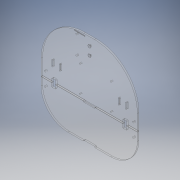
# Autodesk Inventor part: Chassis
Saved by Autodesk Inventor 2019.4 (Build 234330000, 330)
## iProperties
Created: 2020-09-02
Part Number: Chassis
Material: PMMA Plastic
Document SubType Name: Modeling
Designer: Mike Angus
Density: 1.188 g/cm^3
Appearance: Polycarbonate - Clear
ch_motorHoleSpacing: 25,200 mm
ch_motorHoleOffset: 7,500 mm
ch_motorHoleDiam: 3,000 mm
Author: Mike Angus
Autodesk Inventor part; units mm, degrees
ref_plane "YZ Plane" through (0, 0, 0) normal (1, 0, 0) x (0, 1, 0)
ref_plane "XZ Plane" through (0, 0, 0) normal (0, 1, 0) x (-1, 0, 0)
ref_plane "XY Plane" through (0, 0, 0) normal (0, 0, 1) x (1, 0, 0)
sketch "Profielt" plane through (0, 0, 0) normal (0, 0, 1) x (1, 0, 0)
  line L0 (90, 0) -> (-90, 0)
  line L1 (-90, 0) -> (-90, -65)
  line L2 (-90, -65) -> (90, -65)
  line L3 (90, -65) -> (90, 0)
  line L4 (90, 0) -> (90, 110)
  line L5 (90, 110) -> (-90, 110)
  line L6 (-90, 110) -> (-90, 0)
  point P0 (0, 0)
  point P1 (0, 0)
  point P2 (0, 0)
  dimension "d9" = 65
  dimension "d10" = 180
  dimension "d11" = 110
  constraints: 14 end point, 3 perpendicular, 2 parallel, 1 coincident, 1 horizontal, 1 midpoint, 1 vertical
  measures "d9" distance of L2.end L0.start
  measures "d10" distance of L1.end L2.end
  measures "d11" distance of L0.start L4.end
extrude "Front" add sketch "Profielt" along normal blind 3 contours L0 L6 L5 L4
extrude "Rear" add sketch "Profielt" along normal blind 3 separate body contours L3 L2 L1 L0
sketch "Sketch8" plane through (-90, 0, 0) normal (0, 1, 0) x (1, 0, 0)
  line L0 (180, 0) -> (0, 0) projected
  line L1 (0, 0) -> (0, -3) projected
  line L2 (180, -3) -> (0, -3) projected
  line L3 (180, 0) -> (180, -3) projected
  point P0 (90, 0)
extrude "Extrusion10" add sketch "Sketch8" along normal blind 0.4 bodies 2
fillet "Outer Fillets" radius 80 2 edges at (-90, 110, 1.5) (90, 110, 1.5)
fillet "Outer Fillets" radius 50 2 edges at (90, -65, 1.5) (-90, -65, 1.5)
sketch "Sketch2" plane through (0, 0, 3) normal (0, 0, 1) x (1, 0, 0)
  line L0 (0, 0) -> (-82.5, 0) construction
  line L1 (-82.5, -12.6) -> (-82.5, 12.6) construction
  circle A0 centre (-82.5, 12.6) radius 1.5
  circle A1 centre (-82.5, -12.6) radius 1.5
  line L2 (0, 0) -> (0, -16.3555) construction
  circle A2 centre (82.5, 12.6) radius 1.5
  circle A3 centre (82.5, -12.6) radius 1.5
  dimension "d12" = 82.5
  dimension "d13" = 25.2
  dimension "d14" = 3
  constraints: 6 end point, 4 centre point, 2 coincident, 2 symmetric about line, 2 vertical, 1 equal radius, 1 horizontal, 1 midpoint, 2 other
  measures "d12" distance of L0.end L0.start
  measures "d13" distance of L1.start L1.end
  measures "d14" diameter of A0
extrude "Motor Holes" cut sketch "Sketch2" against normal through all bodies 2 1
sketch "Sketch3" plane through (0, 0, 3) normal (0, 0, 1) x (1, 0, 0)
  line L0 (40.5, 57) -> (-17.5, 57) construction
  line L1 (-17.5, 57) -> (-17.5, 8) construction
  line L2 (-17.5, 8) -> (40.5, 8) construction
  line L3 (40.5, 8) -> (40.5, 57) construction
  circle A0 centre (40.5, 8) radius 1.25
  circle A1 centre (-17.5, 8) radius 1.25
  circle A2 centre (-17.5, 57) radius 1.25
  circle A3 centre (40.5, 57) radius 1.25
  line L4 (0, 8) -> (0, 0) construction
  point P0 (11.5, 8)
  dimension "d18" = 49
  dimension "d19" = 58
  dimension "d20" = 2.5
  dimension "d21" = 2.5
  dimension "d22" = 2.5
  dimension "d23" = 2.5
  dimension "d26" = 8
  dimension "d27" = 11.5
  constraints: 10 end point, 5 coincident, 4 centre point, 2 parallel, 1 horizontal, 1 midpoint, 1 perpendicular, 1 point on line, 1 vertical
  measures "d18" distance of L0.end L1.end
  measures "d19" distance of L0.start L0.end
  measures "d20" diameter of A0
  measures "d21" diameter of A1
  measures "d22" diameter of A2
  measures "d23" diameter of A3
  measures "d26" distance of L4.start L4.end
  measures "d27" distance from line of L4 point (11.5, 8)
extrude "Pi holes" cut sketch "Sketch3" against normal through all bodies 1
sketch "Castor holes/nuts" plane through (0, 0, 3) normal (0, 0, 1) x (1, 0, 0)
  line L0 (0, 0) -> (0, 94) construction
  line L1 (0, 78.6) -> (0, 94) construction
  circle A0 centre (0, 78.6) radius 1.25
  circle A1 centre (0, 94) radius 1.25
  line L2 (-2.829, 94) -> (-1.4145, 96.45)
  line L3 (-1.4145, 96.45) -> (1.4145, 96.45)
  line L4 (1.4145, 96.45) -> (2.829, 94)
  line L5 (2.829, 94) -> (1.4145, 91.55)
  line L6 (1.4145, 91.55) -> (-1.4145, 91.55)
  line L7 (-1.4145, 91.55) -> (-2.829, 94)
  line L8 (1.4145, 76.15) -> (-1.4145, 76.15)
  line L9 (-1.4145, 76.15) -> (-2.829, 78.6)
  line L10 (-2.829, 78.6) -> (-1.4145, 81.05)
  line L11 (-1.4145, 81.05) -> (1.4145, 81.05)
  line L12 (1.4145, 81.05) -> (2.829, 78.6)
  line L13 (2.829, 78.6) -> (1.4145, 76.15)
  dimension "d28" = 94
  dimension "d29" = 15.4
  dimension "d30" = 2.5
  dimension "d31" = 2.5
  dimension "d34" = 4.9
  dimension "d35" = 4.9
  constraints: 28 end point, 4 coincident, 2 centre point, 2 horizontal, 2 vertical, 26 other
  measures "d28" distance of L0.end L0.start
  measures "d29" distance of L0.end L1.start
  measures "d30" diameter of A0
  measures "d31" diameter of A1
  measures "d34" distance between parallel lines of L3 L6
  measures "d35" distance between parallel lines of L8 L11
extrude "Castor holes" cut sketch "Castor holes/nuts" against normal through all contours A0 | A1 bodies 1
extrude "Castor nut cuts" cut sketch "Castor holes/nuts" against normal blind 1 bodies 1
sketch "Camera holes and slot" plane through (0, 0, 0) normal (0, 0, -1) x (-1, 0, 0)
  line L0 (0, 0) -> (0, 102) construction
  line L1 (0, 102) -> (23.73, 102) construction
  line L2 (23.73, 102) -> (23.73, 67) construction
  circle A0 centre (23.73, 67) radius 1.5
  circle A1 centre (23.73, 102) radius 1.5
  line L3 (8.23, 105.8) -> (27.73, 105.8)
  line L4 (27.73, 105.8) -> (27.73, 107.05)
  line L5 (27.73, 107.05) -> (8.23, 107.05)
  line L6 (8.23, 107.05) -> (8.23, 105.8)
  line L7 (8.23, 105.8) -> (27.73, 107.05) construction
  line L8 (27.73, 105.8) -> (8.23, 107.05) construction
  line L9 (23.73, 102) -> (27.73, 102) construction
  line L10 (27.73, 102) -> (27.73, 105.8) construction
  point P0 (17.98, 106.425)
  dimension "d38" = 102
  dimension "d39" = 23.73
  dimension "d40" = 35
  dimension "d41" = 3
  dimension "d42" = 3
  dimension "d45" = 19.5
  dimension "d46" = 1.25
  dimension "d47" = 4
  dimension "d48" = 3.8
  constraints: 22 end point, 3 perpendicular, 2 centre point, 2 coincident, 2 horizontal, 2 midpoint, 2 parallel, 2 vertical
  measures "d38" distance of L0.start L0.end
  measures "d39" distance of L0.end L1.end
  measures "d40" distance of L1.end L2.end
  measures "d41" diameter of A0
  measures "d42" diameter of A1
  measures "d45" distance of L5.end L4.end
  measures "d46" distance of L3.end L4.end
  measures "d47" distance of L9.start L9.end
  measures "d48" distance of L9.end L3.end
extrude "Extrusion7" cut sketch "Camera holes and slot" against normal through all contours A0 | A1 bodies 1
sketch "Sketch6" plane through (0, 0, 3) normal (0, 0, 1) x (1, 0, 0)
  line L0 (-8.23, 105.8) -> (-27.73, 105.8) projected
  line L1 (-8.23, 107.05) -> (-8.23, 105.8) projected
  line L2 (-27.73, 107.05) -> (-8.23, 107.05) projected
  line L3 (-27.73, 105.8) -> (-27.73, 107.05) projected
  point P0 (0, 0)
extrude "Extrusion8" cut sketch "Sketch6" against normal blind 0.5 bodies 1
sketch "Slots" plane through (0, 0, 3) normal (0, 0, 1) x (1, 0, 0)
  line L0 (-64, -7.1) -> (-69, -7.1)
  line L1 (-70, -6.1) -> (-70, 6.9)
  line L2 (-69, 7.9) -> (-64, 7.9)
  line L3 (-63, 6.9) -> (-63, -6.1)
  line L4 (-63, -7.1) -> (-70, 7.9) construction
  line L5 (-70, -7.1) -> (-63, 7.9) construction
  line L6 (-70, 0.4) -> (0, 0.4) construction
  arc A0 (-64, -7.1) -> (-63, -6.1) centre (-64, -6.1) ccw
  arc A1 (-70, -6.1) -> (-69, -7.1) centre (-69, -6.1) ccw
  arc A2 (-69, 7.9) -> (-70, 6.9) centre (-69, 6.9) ccw
  arc A3 (-63, 6.9) -> (-64, 7.9) centre (-64, 6.9) ccw
  line L7 (0, 0.4) -> (0, -65) construction
  line L8 (64, -7.1) -> (69, -7.1)
  line L9 (70, -6.1) -> (70, 6.9)
  line L10 (69, 7.9) -> (64, 7.9)
  line L11 (63, 6.9) -> (63, -6.1)
  line L12 (63, -7.1) -> (70, 7.9) construction
  line L13 (70, -7.1) -> (63, 7.9) construction
  arc A4 (63, -6.1) -> (64, -7.1) centre (64, -6.1) ccw
  arc A5 (69, -7.1) -> (70, -6.1) centre (69, -6.1) ccw
  arc A6 (70, 6.9) -> (69, 7.9) centre (69, 6.9) ccw
  arc A7 (64, 7.9) -> (63, 6.9) centre (64, 6.9) ccw
  line L14 (10.5, -1.6) -> (-10.5, -1.6)
  line L15 (-10.5, -1.6) -> (-10.5, 0.4)
  line L16 (-10.5, 0.4) -> (10.5, 0.4)
  line L17 (10.5, 0.4) -> (10.5, -1.6)
  line L18 (10.5, -1.6) -> (-10.5, 0.4) construction
  line L19 (-10.5, -1.6) -> (10.5, 0.4) construction
  line L20 (10.5, -65) -> (-10.5, -65)
  line L21 (-10.5, -65) -> (-10.5, -63)
  line L22 (-10.5, -63) -> (10.5, -63)
  line L23 (10.5, -63) -> (10.5, -65)
  line L24 (10.5, -65) -> (-10.5, -63) construction
  line L25 (-10.5, -65) -> (10.5, -63) construction
  point P0 (70, 0.4)
  point P1 (0, -0.6)
  point P2 (0, -0.6)
  point P3 (0, -64)
  point P4 (0, -64)
  point P5 (0, 0)
  dimension "d51" = 7
  dimension "d52" = 15
  dimension "d53" = 70
  dimension "d54" = 1
  dimension "d55" = 1
  dimension "d56" = 21
  dimension "d57" = 2
  dimension "d58" = 65.4
  dimension "d59" = 21
  dimension "d60" = 2
  dimension "d66" = 0.4
  constraints: 52 end point, 19 point on line, 17 symmetric about line, 16 point on circle, 9 midpoint, 8 centre point, 8 tangent, 6 parallel, 4 horizontal, 3 perpendicular, 2 equal radius, 1 coincident, 1 vertical, 4 other
  measures "d51" distance of L4.end L5.end
  measures "d52" distance of L5.start L4.end
  measures "d53" distance of L6.start L6.end
  measures "d54" radius of A0
  measures "d55" radius of A3
  measures "d56" distance of L14.start L14.end
  measures "d57" distance of L14.end L15.end
  measures "d58" distance of L7.end L6.end
  measures "d59" distance of L21.end L22.end
  measures "d60" distance of L20.end L21.end
  measures "d66" distance from line of point (0, 0) L16
extrude "Velcro batt slot" cut sketch "Slots" against normal through all contours L14 L15 L16 L17 | L20 L21 L22 L23 bodies 2
extrude "Motor slots" cut sketch "Slots" against normal through all contours L0 A1 L1 A2 L2 A3 L3 A0 | A4 L11 A7 L10 A6 L9 A5 L8 bodies 2 1
fillet "Fillet2" radius 1 8 edges at (10.5, -1.6, 1.5) (-10.5, -1.6, 1.5) (-10.5, -65, 1.5) (-10.5, -63, 1.5) (10.5, -63, 1.5) (10.5, -65, 1.5) (10.5, 0.4, 1.5) (-10.5, 0.4, 1.5)
sketch "Sketch9" plane through (0, 0, 3) normal (0, 0, 1) x (1, 0, 0)
  line L0 (0, 0) -> (0, 32) construction
  line L1 (0, 32) -> (-55, 32) construction
  line L2 (-55, 27) -> (-55, 37) construction
  line L3 (-54, 27) -> (-54, 37)
  line L4 (-56, 37) -> (-56, 27)
  arc A0 (-56, 27) -> (-54, 27) centre (-55, 27) ccw
  arc A1 (-54, 37) -> (-56, 37) centre (-55, 37) ccw
  line L5 (-55, 32) -> (-69, 32) construction
  line L6 (-69, 27) -> (-69, 37) construction
  line L7 (-68, 27) -> (-68, 37)
  line L8 (-70, 37) -> (-70, 27)
  arc A2 (-70, 27) -> (-68, 27) centre (-69, 27) ccw
  arc A3 (-68, 37) -> (-70, 37) centre (-69, 37) ccw
  line L9 (55, 27) -> (55, 37) construction
  line L10 (54, 27) -> (54, 37)
  line L11 (56, 37) -> (56, 27)
  arc A4 (54, 27) -> (56, 27) centre (55, 27) ccw
  arc A5 (56, 37) -> (54, 37) centre (55, 37) ccw
  line L12 (55, 32) -> (69, 32) construction
  line L13 (69, 27) -> (69, 37) construction
  line L14 (68, 27) -> (68, 37)
  line L15 (70, 37) -> (70, 27)
  arc A6 (68, 27) -> (70, 27) centre (69, 27) ccw
  arc A7 (70, 37) -> (68, 37) centre (69, 37) ccw
  dimension "d67" = 32
  dimension "d68" = 55
  dimension "d70" = 2
  dimension "d71" = 14
  dimension "d73" = 10
  dimension "d74" = 10
  dimension "d75" = 2
  constraints: 40 end point, 16 point on circle, 14 symmetric about line, 8 centre point, 8 tangent, 3 vertical, 2 midpoint, 2 parallel, 1 horizontal, 1 perpendicular, 4 other
  measures "d67" distance of L0.start L0.end
  measures "d68" distance of L0.end L1.end
  measures "d70" diameter of A1
  measures "d71" distance of L1.end L5.end
  measures "d73" distance of L2.start L2.end
  measures "d74" distance of L6.start L6.end
  measures "d75" distance between parallel lines of L8 L7
extrude "Extrusion11" cut sketch "Sketch9" against normal through all bodies 1
equation "\"d9\" = ch_lengthRear"
equation "\"d10\" = ch_width"
equation "\"d11\" = ch_lengthFront"
equation "\"d64\" = ch_seamKerfCompensation"
equation "\"d4\" = ch_frontFillet"
equation "\"d5\" = ch_rearFillet"
equation "\"d12\" = 0.5 * ch_width - ch_motorHoleOffset"
equation "\"d13\" = ch_motorHoleSpacing"
equation "\"d14\" = ch_motorHoleDiam"
equation "\"d18\" = rpi_holeSpacingWidth"
equation "\"d19\" = rpi_holeSpacingLength"
equation "\"d20\" = ch_piHoleDiam"
equation "\"d21\" = ch_piHoleDiam"
equation "\"d22\" = ch_piHoleDiam"
equation "\"d23\" = ch_piHoleDiam"
equation "\"d26\" = ch_piHoleOffset"
equation "\"d27\" = ch_piHorizOffset"
equation "\"d28\" = ch_castorOffset"
equation "\"d29\" = cs_holeSpacing"
equation "\"d30\" = cs_holeDiam"
equation "\"d31\" = cs_holeDiam"
equation "\"d34\" = ch_castorNutSlotDiam"
equation "\"d35\" = ch_castorNutSlotDiam"
equation "\"d38\" = ch_cameraMountOffset"
equation "\"d39\" = ch_cameraMountSideOffset"
equation "\"d40\" = cs_baseHoleSpacing"
equation "\"d41\" = ch_cameraMountHoleDiam"
equation "\"d42\" = ch_cameraMountHoleDiam"
equation "\"d45\" = ch_irEngraveLength"
equation "\"d46\" = ch_irEngraveWidth"
equation "\"d47\" = 0.5 * cs_bulkThickness - cs_irSlotBackstopWidth"
equation "\"d48\" = cs_irSlotToHoleOffset"
equation "\"d49\" = ch_irEngraveDepth"
equation "\"d51\" = ch_motorWireHoleWidth"
equation "\"d52\" = ch_motorWireHoleLength"
equation "\"d53\" = 0.5 * ch_width - ch_motorWireHoleOffset"
equation "\"d54\" = ch_motorHoleFillet"
equation "\"d55\" = ch_motorHoleFillet"
equation "\"d56\" = ch_strapHoleWidth"
equation "\"d57\" = ch_strapHoleDepth"
equation "\"d58\" = ch_lengthRear + ch_seamKerfCompensation"
equation "\"d59\" = ch_strapHoleWidth"
equation "\"d60\" = ch_strapHoleDepth"
equation "\"d66\" = ch_seamKerfCompensation"
equation "\"d63\" = ch_strapHoleFillet"
equation "\"d67\" = ch_wireWrapSlotYOffset"
equation "\"d68\" = ch_wireWrapSlotXOffset"
equation "\"d70\" = ch_wireWrapSlotWidth"
equation "\"d71\" = ch_wireWrapSlotSpacing"
equation "\"d73\" = ch_wireWrapSlotLength"
equation "\"d74\" = ch_wireWrapSlotLength"
equation "\"d75\" = ch_wireWrapSlotWidth"
equation "\"d76\" = ch_seamKerfCompensation"
equation "\"ch_width\" = 180"
equation "\"ch_lengthRear\" = 65"
equation "\"ch_lengthFront\" = 110"
equation "\"ch_motorHoleSpacing\" = mountWingsHoleSpacing"
equation "\"ch_motorHoleOffset\" = 7.5"
equation "\"ch_motorHoleDiam\" = 3"
equation "\"ch_piHoleOffset\" = 8"
equation "\"ch_piHoleDiam\" = 2.5"
equation "\"ch_piHorizOffset\" = 11.5"
equation "\"ch_castorNutSlotDiam\" = 4.9"
equation "\"ch_cameraMountSideOffset\" = 23.73"
equation "\"ch_cameraMountOffset\" = 102"
equation "\"ch_cameraMountHoleDiam\" = 3"
equation "\"cs_irSlotBoardDepth\" = 1.05"
equation "\"ch_irEngraveDepth\" = 0.5"
equation "\"ch_irEngraveLength\" = 19.5"
equation "\"ch_motorWireHoleWidth\" = 7"
equation "\"ch_motorWireHoleLength\" = 15"
equation "\"ch_motorHoleFillet\" = 1"
equation "\"ch_strapHoleWidth\" = 21"
equation "\"ch_strapHoleDepth\" = 2"
equation "\"ch_strapHoleFillet\" = 1"
equation "\"ch_seamKerfCompensation\" = 0.4"
equation "\"ch_wireWrapSlotWidth\" = 2"
equation "\"ch_wireWrapSlotLength\" = 10"
equation "\"ch_wireWrapSlotYOffset\" = 32"
equation "\"ch_wireWrapSlotXOffset\" = 55"
equation "\"ch_wireWrapSlotSpacing\" = 14"
equation "\"ch_frontFillet\" = 80"
equation "\"ch_rearFillet\" = 50"
equation "\"rpi_holeSpacingWidth\" = 49"
equation "\"rpi_holeSpacingLength\" = 58"
equation "\"ch_castorOffset\" = 94"
equation "\"cs_holeSpacing\" = 15.4"
equation "\"cs_holeDiam\" = 2.5"
equation "\"cs_baseHoleSpacing\" = 35"
equation "\"ch_irEngraveWidth\" = 1.25"
equation "\"cs_bulkThickness\" = 12"
equation "\"cs_irSlotBackstopWidth\" = 2"
equation "\"cs_irSlotToHoleOffset\" = 3.8"
equation "\"ch_motorWireHoleOffset\" = 20"
equation "\"mountWingsHoleSpacing\" = 25.2"
body "Solid1"
body "Solid2"
